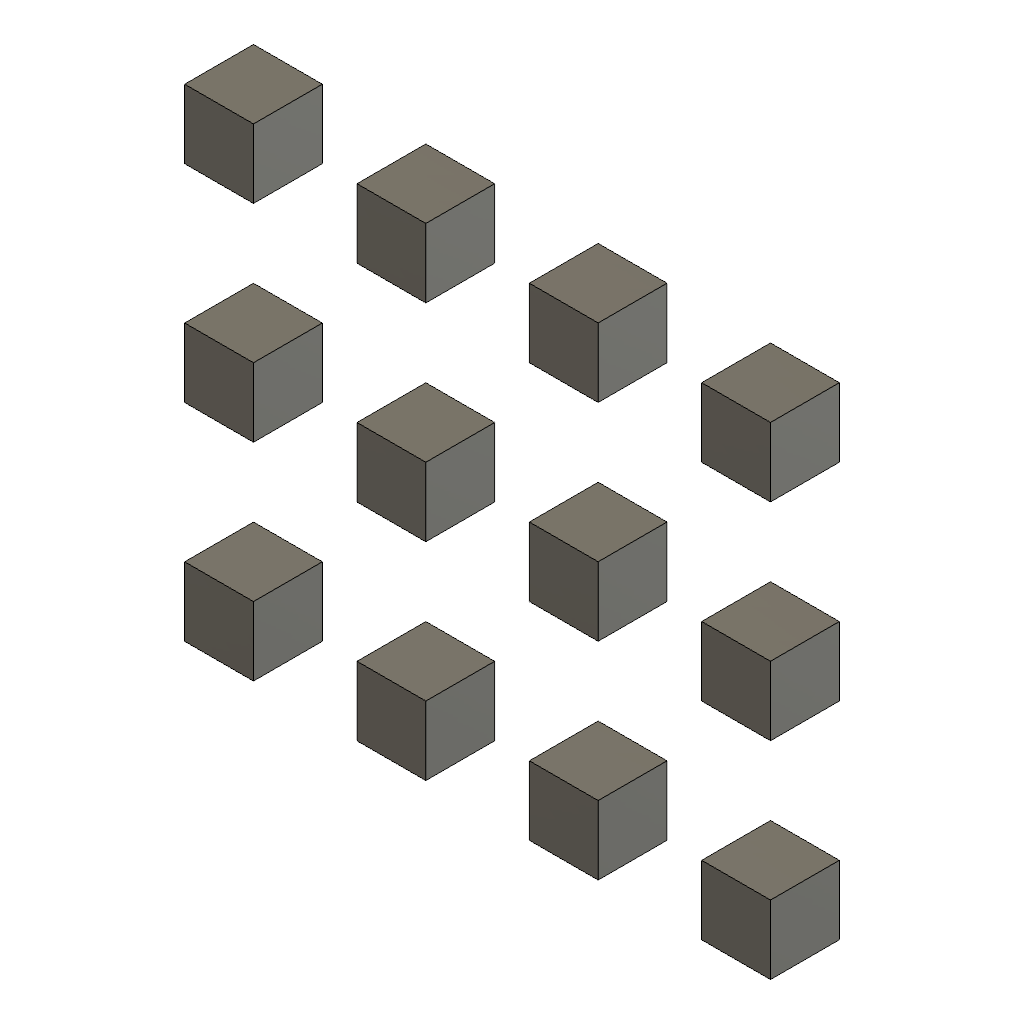
negative_spacing (Autodesk Fusion 360 design; units mm, degrees)
part number: 2026-10-20-22-13-26-246
Autodesk Fusion 360 part; units mm, degrees
sketch "Sketch1" plane through (0, 0, 0) normal (0, 0, 1) x (1, 0, 0)
  line L0 (10, 0) -> (20, 0)
  line L1 (20, 0) -> (20, 10)
  line L2 (20, 10) -> (10, 10)
  line L3 (10, 10) -> (10, 0)
extrude "SeedFeature0" add sketch "Sketch1" along normal blind 10 makes body 1
pattern_linear "ProbeRectangularSymmetryHoldout" count 4 spacing 25 along (-1, 0, 0) both ways count 3 spacing 30 along (0, -1, 0) both ways of bodies 1 makes body 2 at (35, 36.6667, 3.3333) makes body 3 at (10, 36.6667, 3.3333) makes body 4 at (-15, 36.6667, 3.3333) makes body 5 at (-40, 36.6667, 3.3333) makes body 6 at (35, 6.6667, 3.3333) makes body 7 at (-15, 6.6667, 3.3333) makes body 8 at (-40, 6.6667, 3.3333) makes body 9 at (35, -23.3333, 3.3333) makes body 10 at (10, -23.3333, 3.3333) makes body 11 at (-15, -23.3333, 3.3333) makes body 12 at (-40, -23.3333, 3.3333)
named bodies: "SeedBody0", "SeedBody0 (1)", "SeedBody0 (2)", "SeedBody0 (3)", "SeedBody0 (4)", "SeedBody0 (5)", "SeedBody0 (6)", "SeedBody0 (7)", "SeedBody0 (8)", "SeedBody0 (9)", "SeedBody0 (10)", "SeedBody0 (11)"
